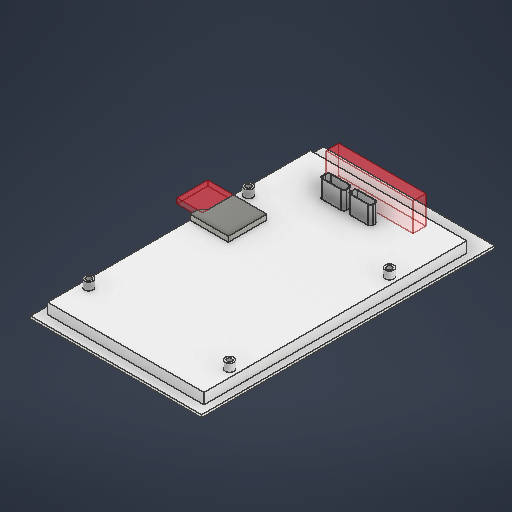
# Autodesk Inventor part: jc4880p443
Saved by Autodesk Inventor 2027.1 (Build 311270010, 270A)
## iProperties
Created: 2026-10-18
Part Number: jc4880p443
Material: ABS 플라스틱
Document SubType Name: Modeling
Designer: work
Density: 1.06 g/cm^3
Appearance: 매끄러움 - 흰색
Author: work
Autodesk Inventor part; units mm, degrees
ref_plane "YZ Plane" through (0, 0, 0) normal (1, 0, 0) x (0, 1, 0)
ref_plane "XZ Plane" through (0, 0, 0) normal (0, 1, 0) x (-1, 0, 0)
ref_plane "XY Plane" through (0, 0, 0) normal (0, 0, 1) x (1, 0, 0)
sketch "스케치1" plane through (0, 0, 0) normal (0, 1, 0) x (-1, 0, 0)
  line L0 (0, 0) -> (66.8, 0)
  line L1 (66.8, 0) -> (66.8, -114.3)
  line L2 (66.8, -114.3) -> (0, -114.3)
  line L3 (0, -114.3) -> (0, 0)
  dimension "d0" = 66.8
  dimension "d1" = 114.3
  constraints: 8 end point, 2 parallel, 1 horizontal, 1 perpendicular
  measures "d0" distance of L1.end L2.end
  measures "d1" distance of L0.end L1.end
extrude "돌출1" add sketch "스케치1" along normal blind 1
sketch "스케치2" plane through (0, 1, 0) normal (0, 1, 0) x (1, 0, 0)
  line L0 (-63.9, 3.8) -> (-2.9, 3.8)
  line L1 (-2.9, 3.8) -> (-2.9, 106.3)
  line L2 (-2.9, 106.3) -> (-63.9, 106.3)
  line L3 (-63.9, 106.3) -> (-63.9, 3.8)
  line L4 (0, 114.3) -> (-66.8, 114.3) projected
  point P0 (0, 0)
  point P1 (-33.4, 106.3)
  point P2 (-33.4, 114.3)
  dimension "d4" = 61
  dimension "d5" = 102.5
  dimension "d6" = 8
  constraints: 8 end point, 2 midpoint, 2 parallel, 1 horizontal, 1 perpendicular, 1 vertical alignment
  measures "d4" distance of L2.end L1.end
  measures "d5" distance of L1.end L0.end
  measures "d6" distance between parallel lines of L4 L2
extrude "돌출2" add sketch "스케치2" along normal blind 4.2
sketch "스케치3" plane through (0, 5.2, 0) normal (0, 1, 0) x (1, 0, 0)
  line L0 (-60.9, 16.8) -> (-5.9, 16.8) construction
  line L1 (-5.9, 16.8) -> (-5.9, 79.2) construction
  line L2 (-5.9, 79.2) -> (-60.9, 79.2) construction
  line L3 (-60.9, 79.2) -> (-60.9, 16.8) construction
  line L4 (-63.9, 3.8) -> (-2.9, 3.8) projected
  circle A0 centre (-60.9, 16.8) radius 1.7
  circle A1 centre (-60.9, 16.8) radius 1
  point P0 (0, 0)
  point P1 (-33.4, 16.8)
  point P2 (-33.4, 3.8)
  dimension "d9" = 55
  dimension "d10" = 62.4
  dimension "d11" = 13
  dimension "d12" = 3.4
  dimension "d13" = 2
  constraints: 8 end point, 4 coincident, 2 centre point, 2 midpoint, 2 parallel, 1 horizontal, 1 perpendicular, 1 vertical alignment
  measures "d9" distance of L2.end L1.end
  measures "d10" distance of L1.end L0.end
  measures "d11" distance from line of L4 point (-33.4, 16.8)
  measures "d12" diameter of A0
  measures "d13" diameter of A1
extrude "돌출3" add sketch "스케치3" along normal blind 3
pattern_sketch "스케치 연계 패턴1" of "돌출3" from (-60.9, 5.2, -16.8) copies at (-5.9, 5.2, -79.2) at (-5.9, 5.2, -16.8) at (-60.9, 5.2, -79.2)
sketch "스케치4" plane through (0, 5.2, 0) normal (0, 1, 0) x (1, 0, 0)
  line L0 (-45.9, 95.3) -> (-36.9, 95.3)
  line L1 (-36.9, 95.3) -> (-36.9, 92.3)
  line L2 (-36.9, 92.3) -> (-45.9, 92.3)
  line L3 (-45.9, 92.3) -> (-45.9, 95.3)
  line L4 (-2.9, 106.3) -> (-63.9, 106.3) projected
  line L5 (-63.9, 106.3) -> (-63.9, 3.8) projected
  line L6 (-35.4, 95.3) -> (-26.4, 95.3)
  line L7 (-26.4, 95.3) -> (-26.4, 92.3)
  line L8 (-26.4, 92.3) -> (-35.4, 92.3)
  line L9 (-35.4, 92.3) -> (-35.4, 95.3)
  line L10 (-36.7, 95.5) -> (-46.1, 95.5)
  line L11 (-46.1, 95.5) -> (-46.1, 92.1)
  line L12 (-46.1, 92.1) -> (-36.7, 92.1)
  line L13 (-36.7, 92.1) -> (-36.7, 95.5)
  line L14 (-26.6, 95.1) -> (-35.2, 95.1)
  line L15 (-35.2, 95.1) -> (-35.2, 92.5)
  line L16 (-35.2, 92.5) -> (-26.6, 92.5)
  line L17 (-26.6, 92.5) -> (-26.6, 95.1)
  point P0 (0, 0)
  point P1 (-41.4, 95.3)
  point P2 (-45.9, 93.8)
  point P3 (-30.9, 95.3)
  point P4 (-35.4, 93.8)
  dimension "d24" = 9
  dimension "d25" = 3
  dimension "d26" = 11
  dimension "d27" = 18
  dimension "d28" = 9
  dimension "d29" = 3
  dimension "d30" = 1.5
  dimension "d31" = 0.2
  dimension "d32" = 0.2
  constraints: 32 end point, 8 parallel, 4 midpoint, 4 perpendicular, 2 horizontal, 1 point on line, 6 other
  measures "d24" distance of L1.end L2.end
  measures "d25" distance of L0.end L1.end
  measures "d26" distance from line of L4 point (-41.4, 95.3)
  measures "d27" distance from line of L5 point (-45.9, 93.8)
  measures "d28" distance of L7.end L8.end
  measures "d29" distance of L6.end L7.end
  measures "d30" distance between parallel lines of L9 L1
  measures "d31" distance between parallel lines of L0 L10
  measures "d32" distance between parallel lines of L6 L14
extrude "돌출4" add sketch "스케치4" along normal blind 7 separate body
fillet "모깎기1" radius 1 16 edges at (-36.7, 8.7, -95.5) (-46.1, 8.7, -95.5) (-36.9, 8.7, -95.3) (-35.4, 8.7, -95.3) (-46.1, 8.7, -92.1) (-45.9, 8.7, -95.3) (-45.9, 8.7, -92.3) (-26.6, 8.7, -92.5) (-26.6, 8.7, -95.1) (-35.2, 8.7, -95.1) (-35.2, 8.7, -92.5) (-36.7, 8.7, -92.1) (-35.4, 8.7, -92.3) (-36.9, 8.7, -92.3) (-26.4, 8.7, -95.3) (-26.4, 8.7, -92.3)
sketch "스케치5" plane through (0, 5.2, 0) normal (0, 1, 0) x (1, 0, 0)
  line L0 (-49.8, 103.3) -> (-15.8, 103.3)
  line L1 (-15.8, 103.3) -> (-15.8, 98.3)
  line L2 (-15.8, 98.3) -> (-49.8, 98.3)
  line L3 (-49.8, 98.3) -> (-49.8, 103.3)
  line L4 (-66.8, 114.3) -> (-66.8, 0) projected
  line L5 (-2.9, 106.3) -> (-63.9, 106.3) projected
  point P0 (0, 0)
  point P1 (-49.8, 100.8)
  dimension "d36" = 34
  dimension "d37" = 5
  dimension "d38" = 17
  dimension "d39" = 3
  constraints: 8 end point, 2 parallel, 1 horizontal, 1 midpoint, 1 perpendicular
  measures "d36" distance of L1.end L2.end
  measures "d37" distance of L0.end L1.end
  measures "d38" distance from line of L4 point (-49.8, 100.8)
  measures "d39" distance between parallel lines of L0 L5
extrude "돌출5" add sketch "스케치5" along normal blind 11 separate body
sketch "스케치6" plane through (0, 5.2, 0) normal (0, 1, 0) x (1, 0, 0)
  line L0 (-63.9, 59.3) -> (-48.9, 59.3)
  line L1 (-48.9, 59.3) -> (-48.9, 74.3)
  line L2 (-48.9, 74.3) -> (-63.9, 74.3)
  line L3 (-63.9, 74.3) -> (-63.9, 59.3)
  line L4 (-63.9, 62.3) -> (-61.9, 64.3)
  line L5 (-61.9, 64.3) -> (-61.9, 74.3)
  circle A0 centre (-60.9, 16.8) radius 1.7 projected
  line L6 (-2.9, 3.8) -> (-2.9, 106.3) projected
  line L7 (-2.9, 106.3) -> (-63.9, 106.3) projected
  line L8 (-63.9, 106.3) -> (-63.9, 3.8) projected
  line L9 (-63.9, 3.8) -> (-2.9, 3.8) projected
  circle A1 centre (-5.9, 79.2) radius 1.7 projected
  circle A2 centre (-5.9, 16.8) radius 1.7 projected
  circle A3 centre (-60.9, 79.2) radius 1.7 projected
  point P0 (0, 0)
  dimension "d42" = 15
  dimension "d43" = 15
  dimension "d44" = 45
  dimension "d45" = 3
  dimension "d46" = 2
  dimension "d47" = 32
  constraints: 12 end point, 3 point on line, 2 parallel, 2 perpendicular, 1 horizontal
  measures "d42" distance of L2.end L1.end
  measures "d43" distance of L1.end L0.end
  measures "d44" angle of L5 L4
  measures "d45" distance of L0.start L4.start
  measures "d46" distance between parallel lines of L3 L5
  measures "d47" distance between parallel lines of L7 L2
extrude "돌출6" add sketch "스케치6" along normal blind 2 separate body contours L3 L4 L5 L2 L1 L0
sketch "스케치7" plane through (-61.9, 5.2, -74.3) normal (-1, 0, 0) x (0, 0, 1)
  line L0 (70.5, 0) -> (-32, 0) projected
  line L1 (12, 2) -> (15, 2) projected
  line L2 (0, 0) -> (15, 0)
  line L3 (15, 0) -> (15, 2)
  line L4 (15, 2) -> (0, 2)
  line L5 (0, 2) -> (0, 0)
  line L6 (-32, 0) -> (70.5, 0) projected
  line L7 (12, 0) -> (12, 2) projected
  line L8 (12, 2) -> (12, 0)
  point P0 (74.3, -5.2)
  constraints: 10 end point, 3 equal length, 3 point on line, 1 horizontal, 1 perpendicular
extrude "돌출7" add sketch "스케치7" along normal blind 10 separate body contours L0 L5 L4 L7
